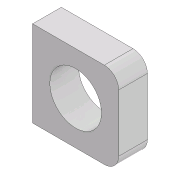
# Autodesk Inventor part: Hülse_1
Saved by Autodesk Inventor 2020.1 (Build 241239000, 239)
## iProperties
Created: 2020-09-10
Part Number: Hülse_1
Material: Generisch
Document SubType Name: Modeling
Designer: s5chfeis
Density: 1 g/cm^3
Appearance: Vorgabe
Author: s5chfeis
Autodesk Inventor part; units mm, degrees
ref_plane "YZ Plane" through (0, 0, 0) normal (1, 0, 0) x (0, 1, 0)
ref_plane "XZ Plane" through (0, 0, 0) normal (0, 1, 0) x (-1, 0, 0)
ref_plane "XY Plane" through (0, 0, 0) normal (0, 0, 1) x (1, 0, 0)
sketch "Skizze1" plane through (0, 0, 0) normal (0, 0, 1) x (1, 0, 0)
  line L0 (0, 0) -> (15, 0)
  line L1 (15, 0) -> (15, 15)
  line L2 (15, 15) -> (0, 15)
  line L3 (0, 15) -> (0, 0)
  dimension "d0" = 15
  dimension "d1" = 15
  constraints: 8 end point, 2 parallel, 1 horizontal, 1 perpendicular
  measures "d0" distance of L2.end L1.end
  measures "d1" distance of L1.end L0.end
extrude "Extrusion1" add sketch "Skizze1" along normal blind 5
sketch "Skizze2" plane through (0, 0, 5) normal (0, 0, 1) x (1, 0, 0)
  line L0 (15, 15) -> (0, 15) construction
  line L1 (0, 0) -> (15, 15) construction
  line L2 (0, 0) -> (15, 0) construction
  line L3 (0, 15) -> (15, 0) construction
  point P0 (7.5, 7.5)
  constraints: 4 end point, 1 midpoint
hole "Bohrung1" at (7.5, 7.5, 5) direction (0, 0, -1) diameter 9 depth 27.3 tip angle 118 clearance for "Flachkopfsenkschraube DIN EN ISO 2009" size "M8" standard "DIN"
fillet "Rundung1" radius 2.5 2 edges at (15, 15, 2.5) (15, 0, 2.5)
